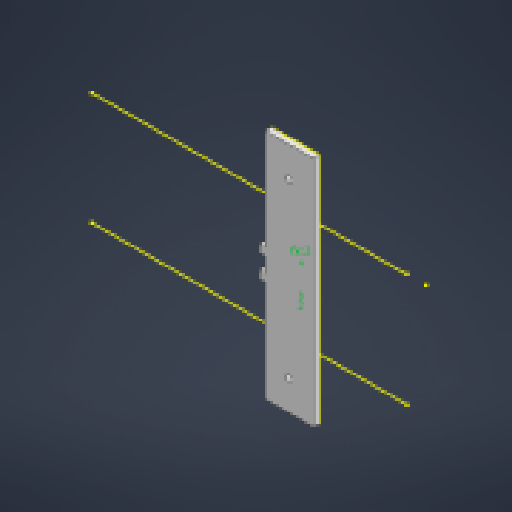
# Autodesk Inventor part: support_peltier
Saved by Autodesk Inventor 2026.1 (Build 301233020, 233B)
## iProperties
Created: 2026-06-04
Part Number: support_peltier
Material: Générique
Document SubType Name: Modeling
Designer: matpo
Density: 1 g/cm^3
Appearance: Par défaut
Author: matpo
Autodesk Inventor part; units mm, degrees
sketch "Esquisse1" plane through (0, 0, 0) normal (0, 0, 1) x (1, 0, 0)
  line L0 (-36.9758, 40) -> (-36.9758, 0) projected
  line L1 (-36.9758, 40) -> (-151.8174, 40) projected
  line L2 (-151.8174, 0) -> (-151.8174, 40) projected
  line L3 (-36.9758, 0) -> (-151.8174, 0) projected
  circle A0 centre (-86.9758, 20) radius 2.1 projected
  line L4 (-102.9758, 40) -> (-70.9758, 40)
  line L5 (-70.9758, 40) -> (-70.9758, 0)
  line L6 (-70.9758, 0) -> (-102.9758, 0)
  line L7 (-102.9758, 0) -> (-102.9758, 40)
  line L8 (-102.9758, 40) -> (-70.9758, 0) construction
  line L9 (-70.9758, 40) -> (-102.9758, 0) construction
  line L10 (-36.9758, -75) -> (-36.9758, -115) projected
  line L11 (-36.9758, -75) -> (-151.8174, -75) projected
  line L12 (-151.8174, -115) -> (-151.8174, -75) projected
  line L13 (-36.9758, -115) -> (-151.8174, -115) projected
  circle A1 centre (-86.9758, -95) radius 2.1 projected
  line L14 (-70.9758, -75) -> (-102.9758, -75)
  line L15 (-102.9758, -75) -> (-102.9758, -115)
  line L16 (-102.9758, -115) -> (-70.9758, -115)
  line L17 (-70.9758, -115) -> (-70.9758, -75)
  line L18 (-70.9758, -75) -> (-102.9758, -115) construction
  line L19 (-102.9758, -75) -> (-70.9758, -115) construction
  line L20 (-70.9758, -75) -> (-70.9758, 0)
  line L21 (-102.9758, 0) -> (-102.9758, -75)
  line L22 (-86.9758, 20) -> (-86.9758, -37.5) construction
  line L23 (-86.9758, -37.5) -> (-86.9758, -95) construction
  line L24 (-102.9758, -42.5) -> (-102.9758, -32.5)
  point P0 (0, 0)
  point P1 (-102.9758, -45)
  dimension "d0" = 32
  constraints: 34 end point, 4 midpoint, 4 parallel, 3 collinear, 3 perpendicular, 3 point on line, 2 horizontal, 1 vertical, 1 vertical alignment
  measures "d0" distance between parallel lines of L7 L5
extrude "Extrusion1" add sketch "Esquisse1" along normal blind 4
ref_plane "Plan de construction1" through (-222.4439, 0, -12) normal (0, 0, -1) x (0, 1, 0)
sketch "Esquisse6" plane through (0, 0, 0) normal (0, 0, -1) x (-1, 0, 0)
  line L0 (13.0323, 0) -> (222.4439, 0) projected
  line L1 (70.9758, -115) -> (70.9758, 40) projected
  line L2 (13.0323, -75) -> (222.4439, -75) projected
  line L3 (102.9758, 0) -> (102.9758, -75) projected
  line L4 (102.9758, -32.5) -> (102.9758, -42.5) projected
  line L5 (102.9758, 0) -> (102.9758, -75) projected
  line L6 (106.9758, -32.5) -> (102.9758, -32.5) projected
  line L7 (102.9758, -27.5) -> (106.9758, -27.5) projected
  line L8 (106.9758, -27.5) -> (106.9758, -32.5) projected
  line L9 (98.9758, -42.5) -> (106.9758, -42.5) projected
  line L10 (106.9758, -42.5) -> (106.9758, -47.5) projected
  line L11 (106.9758, -47.5) -> (102.9758, -47.5) projected
  point P0 (0, 0)
  point P1 (102.9758, -115)
  point P2 (102.9758, 40)
ref_plane "Plan de construction2" through (-222.4439, 0, -12) normal (0, 0, -1) x (0, 1, 0)
ref_plane "Plan de construction3" through (-222.4439, 0, -12) normal (0, 0, -1) x (0, 1, 0)
